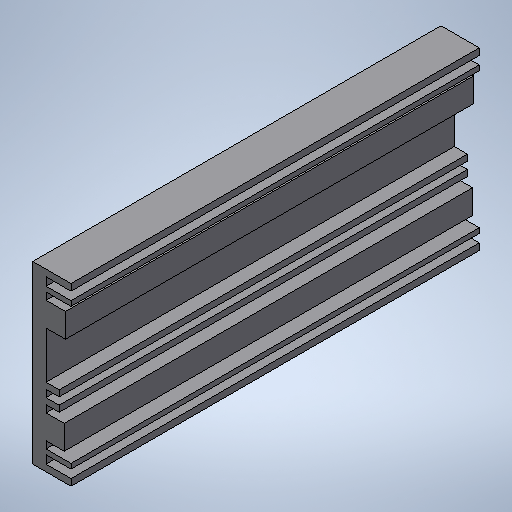
# Autodesk Inventor part: Standard
Saved by Autodesk Inventor 2025.3 (Build 293356000, 356)
## iProperties
RuleStatus: InUse
Created: 2026-11-10
Project: COMMON
Material: Generic
Catalog Web Link: https://www.janelia.org/
Vendor: HHMI: JRC - JET
Document SubType Name: Modeling
Designer: sawtelles
Density: 1 g/cm^3
Appearance: Default
AfterDocSave0: file://Part Number Cleaner
LAB/DEPT: COMMON
REQUESTING SCIENTIST: COMMON
DESIGN DEPARTMENT: HHMI: JRC - ID&F
ALTERED ITEM PART NUMBER: N/A
ALTERED ITEM VENDOR: N/A
ALTERED ITEM DESCRIPTION: N/A
Title: Standard
Author: sawtelles
Revision Number: 0
Autodesk Inventor part; units mm, degrees
ref_plane "YZ Plane" through (0, 0, 0) normal (1, 0, 0) x (0, 1, 0)
ref_plane "XZ Plane" through (0, 0, 0) normal (0, 1, 0) x (-1, 0, 0)
ref_plane "XY Plane" through (0, 0, 0) normal (0, 0, 1) x (1, 0, 0)
sketch "Sketch1" plane through (0, 0, 0) normal (0, 0, 1) x (1, 0, 0)
  line L0 (0, 0) -> (0, 43.688)
  line L1 (0, 43.688) -> (9.525, 43.688)
  line L2 (9.525, 43.688) -> (9.525, 42.037)
  line L3 (9.525, 42.037) -> (3.302, 42.037)
  line L4 (3.302, 42.037) -> (3.302, 40.005)
  line L5 (3.302, 40.005) -> (9.525, 40.005)
  line L6 (9.525, 40.005) -> (9.525, 38.7604)
  line L7 (9.525, 38.7604) -> (3.302, 38.7604)
  line L8 (3.302, 38.7604) -> (3.302, 36.9824)
  line L9 (3.302, 36.9824) -> (8.1534, 36.9824)
  line L10 (8.1534, 36.9824) -> (8.1534, 30.988)
  line L11 (8.1534, 30.988) -> (3.302, 30.988)
  line L12 (3.302, 30.988) -> (3.302, 19.304)
  line L13 (3.302, 19.304) -> (6.5786, 19.304)
  line L14 (6.5786, 19.304) -> (6.5786, 17.78)
  line L15 (6.5786, 17.78) -> (3.302, 17.78)
  line L16 (3.302, 17.78) -> (3.302, 16.002)
  line L17 (3.302, 16.002) -> (6.5786, 16.002)
  line L18 (6.5786, 16.002) -> (6.5786, 14.478)
  line L19 (6.5786, 14.478) -> (3.302, 14.478)
  line L20 (3.302, 14.478) -> (3.302, 12.7)
  line L21 (3.302, 12.7) -> (7.8486, 12.7)
  line L22 (7.8486, 12.7) -> (7.8486, 6.7056)
  line L23 (7.8486, 6.7056) -> (3.302, 6.7056)
  line L24 (3.302, 6.7056) -> (3.302, 4.9276)
  line L25 (3.302, 4.9276) -> (9.525, 4.9276)
  line L26 (9.525, 4.9276) -> (9.525, 3.683)
  line L27 (9.525, 3.683) -> (3.302, 3.683)
  line L28 (3.302, 3.683) -> (3.302, 1.651)
  line L29 (3.302, 1.651) -> (9.525, 1.651)
  line L30 (9.525, 1.651) -> (9.525, 0)
  line L31 (9.525, 0) -> (0, 0)
  point P0 (9.525, 1.651)
  point P1 (3.302, 3.683)
  point P2 (9.525, 4.9276)
  point P3 (3.302, 38.7604)
  point P4 (9.525, 40.005)
  point P5 (3.302, 42.037)
  constraints: 64 end point
extrude "Extrusion1" add sketch "Sketch1" along normal blind 101.6
body "Solid1"
